DiscoEncoder_30ranuras (Autodesk Fusion 360 design; units mm, degrees)
part number: 2026-10-14-20-40-18-868
Autodesk Fusion 360 part; units mm, degrees
sketch "Boceto6" plane through (0, 0, 0) normal (0, 0, 1) x (1, 0, 0)
  circle A0 centre (0, 0) radius 10
extrude "Extruir6" add sketch "Boceto6" along normal blind 3
sketch "Boceto7" plane through (0, 0, 0) normal (0, 0, 1) x (1, 0, 0)
  arc A0 (2.0347, -1.85) -> (2.0347, 1.85) centre (0, 0) ccw
  line L0 (2.0347, 1.85) -> (-2.0347, 1.85)
  arc A1 (-2.0347, 1.85) -> (-2.0347, -1.85) centre (0, 0) ccw
  line L1 (-2.0347, -1.85) -> (2.0347, -1.85)
extrude "Extruir7" cut sketch "Boceto7" along normal blind 4
sketch "Boceto8" plane through (0, 0, 0) normal (0, 0, 1) x (1, 0, 0)
  arc A0 (6.4911, -0.3402) -> (6.4911, 0.3402) centre (0, 0) ccw
  line L0 (6.4911, 0.3402) -> (8.9877, 0.471)
  arc A1 (8.9877, -0.471) -> (8.9877, 0.471) centre (0, 0) ccw
  line L1 (8.9877, -0.471) -> (6.4911, -0.3402)
  arc A2 (6.42, 1.0168) -> (6.2785, 1.6823) centre (0, 0) ccw
  line L2 (6.2785, 1.6823) -> (8.6933, 2.3294)
  arc A3 (8.8892, 1.4079) -> (8.6933, 2.3294) centre (0, 0) ccw
  line L3 (8.8892, 1.4079) -> (6.42, 1.0168)
  arc A4 (6.0683, 2.3294) -> (5.7915, 2.9509) centre (0, 0) ccw
  line L4 (5.7915, 2.9509) -> (8.0191, 4.0859)
  arc A5 (8.4022, 3.2253) -> (8.0191, 4.0859) centre (0, 0) ccw
  line L5 (8.4022, 3.2253) -> (6.0683, 2.3294)
  arc A6 (5.4514, 3.5402) -> (5.0514, 4.0906) centre (0, 0) ccw
  line L6 (5.0514, 4.0906) -> (6.9943, 5.6639)
  arc A7 (7.548, 4.9018) -> (6.9943, 5.6639) centre (0, 0) ccw
  line L7 (7.548, 4.9018) -> (5.4514, 3.5402)
  arc A8 (4.5962, 4.5962) -> (4.0906, 5.0514) centre (0, 0) ccw
  line L8 (4.0906, 5.0514) -> (5.6639, 6.9943)
  arc A9 (6.364, 6.364) -> (5.6639, 6.9943) centre (0, 0) ccw
  line L9 (6.364, 6.364) -> (4.5962, 4.5962)
  arc A10 (3.5402, 5.4514) -> (2.9509, 5.7915) centre (0, 0) ccw
  line L10 (2.9509, 5.7915) -> (4.0859, 8.0191)
  arc A11 (4.9018, 7.548) -> (4.0859, 8.0191) centre (0, 0) ccw
  line L11 (4.9018, 7.548) -> (3.5402, 5.4514)
  arc A12 (2.3294, 6.0683) -> (1.6823, 6.2785) centre (0, 0) ccw
  line L12 (1.6823, 6.2785) -> (2.3294, 8.6933)
  arc A13 (3.2253, 8.4022) -> (2.3294, 8.6933) centre (0, 0) ccw
  line L13 (3.2253, 8.4022) -> (2.3294, 6.0683)
  arc A14 (1.0168, 6.42) -> (0.3402, 6.4911) centre (0, 0) ccw
  line L14 (0.3402, 6.4911) -> (0.471, 8.9877)
  arc A15 (1.4079, 8.8892) -> (0.471, 8.9877) centre (0, 0) ccw
  line L15 (1.4079, 8.8892) -> (1.0168, 6.42)
  arc A16 (-0.3402, 6.4911) -> (-1.0168, 6.42) centre (0, 0) ccw
  line L16 (-1.0168, 6.42) -> (-1.4079, 8.8892)
  arc A17 (-0.471, 8.9877) -> (-1.4079, 8.8892) centre (0, 0) ccw
  line L17 (-0.471, 8.9877) -> (-0.3402, 6.4911)
  arc A18 (-1.6823, 6.2785) -> (-2.3294, 6.0683) centre (0, 0) ccw
  line L18 (-2.3294, 6.0683) -> (-3.2253, 8.4022)
  arc A19 (-2.3294, 8.6933) -> (-3.2253, 8.4022) centre (0, 0) ccw
  line L19 (-2.3294, 8.6933) -> (-1.6823, 6.2785)
  arc A20 (-2.9509, 5.7915) -> (-3.5402, 5.4514) centre (0, 0) ccw
  line L20 (-3.5402, 5.4514) -> (-4.9018, 7.548)
  arc A21 (-4.0859, 8.0191) -> (-4.9018, 7.548) centre (0, 0) ccw
  line L21 (-4.0859, 8.0191) -> (-2.9509, 5.7915)
  arc A22 (-4.0906, 5.0514) -> (-4.5962, 4.5962) centre (0, 0) ccw
  line L22 (-4.5962, 4.5962) -> (-6.364, 6.364)
  arc A23 (-5.6639, 6.9943) -> (-6.364, 6.364) centre (0, 0) ccw
  line L23 (-5.6639, 6.9943) -> (-4.0906, 5.0514)
  arc A24 (-5.0514, 4.0906) -> (-5.4514, 3.5402) centre (0, 0) ccw
  line L24 (-5.4514, 3.5402) -> (-7.548, 4.9018)
  arc A25 (-6.9943, 5.6639) -> (-7.548, 4.9018) centre (0, 0) ccw
  line L25 (-6.9943, 5.6639) -> (-5.0514, 4.0906)
  arc A26 (-5.7915, 2.9509) -> (-6.0683, 2.3294) centre (0, 0) ccw
  line L26 (-6.0683, 2.3294) -> (-8.4022, 3.2253)
  arc A27 (-8.0191, 4.0859) -> (-8.4022, 3.2253) centre (0, 0) ccw
  line L27 (-8.0191, 4.0859) -> (-5.7915, 2.9509)
  arc A28 (-6.2785, 1.6823) -> (-6.42, 1.0168) centre (0, 0) ccw
  line L28 (-6.42, 1.0168) -> (-8.8892, 1.4079)
  arc A29 (-8.6933, 2.3294) -> (-8.8892, 1.4079) centre (0, 0) ccw
  line L29 (-8.6933, 2.3294) -> (-6.2785, 1.6823)
  arc A30 (-6.4911, 0.3402) -> (-6.4911, -0.3402) centre (0, 0) ccw
  line L30 (-6.4911, -0.3402) -> (-8.9877, -0.471)
  arc A31 (-8.9877, 0.471) -> (-8.9877, -0.471) centre (0, 0) ccw
  line L31 (-8.9877, 0.471) -> (-6.4911, 0.3402)
  arc A32 (-6.42, -1.0168) -> (-6.2785, -1.6823) centre (0, 0) ccw
  line L32 (-6.2785, -1.6823) -> (-8.6933, -2.3294)
  arc A33 (-8.8892, -1.4079) -> (-8.6933, -2.3294) centre (0, 0) ccw
  line L33 (-8.8892, -1.4079) -> (-6.42, -1.0168)
  arc A34 (-6.0683, -2.3294) -> (-5.7915, -2.9509) centre (0, 0) ccw
  line L34 (-5.7915, -2.9509) -> (-8.0191, -4.0859)
  arc A35 (-8.4022, -3.2253) -> (-8.0191, -4.0859) centre (0, 0) ccw
  line L35 (-8.4022, -3.2253) -> (-6.0683, -2.3294)
  arc A36 (-5.4514, -3.5402) -> (-5.0514, -4.0906) centre (0, 0) ccw
  line L36 (-5.0514, -4.0906) -> (-6.9943, -5.6639)
  arc A37 (-7.548, -4.9018) -> (-6.9943, -5.6639) centre (0, 0) ccw
  line L37 (-7.548, -4.9018) -> (-5.4514, -3.5402)
  arc A38 (-4.5962, -4.5962) -> (-4.0906, -5.0514) centre (0, 0) ccw
  line L38 (-4.0906, -5.0514) -> (-5.6639, -6.9943)
  arc A39 (-6.364, -6.364) -> (-5.6639, -6.9943) centre (0, 0) ccw
  line L39 (-6.364, -6.364) -> (-4.5962, -4.5962)
  arc A40 (-3.5402, -5.4514) -> (-2.9509, -5.7915) centre (0, 0) ccw
  line L40 (-2.9509, -5.7915) -> (-4.0859, -8.0191)
  arc A41 (-4.9018, -7.548) -> (-4.0859, -8.0191) centre (0, 0) ccw
  line L41 (-4.9018, -7.548) -> (-3.5402, -5.4514)
  arc A42 (-2.3294, -6.0683) -> (-1.6823, -6.2785) centre (0, 0) ccw
  line L42 (-1.6823, -6.2785) -> (-2.3294, -8.6933)
  arc A43 (-3.2253, -8.4022) -> (-2.3294, -8.6933) centre (0, 0) ccw
  line L43 (-3.2253, -8.4022) -> (-2.3294, -6.0683)
  arc A44 (-1.0168, -6.42) -> (-0.3402, -6.4911) centre (0, 0) ccw
  line L44 (-0.3402, -6.4911) -> (-0.471, -8.9877)
  arc A45 (-1.4079, -8.8892) -> (-0.471, -8.9877) centre (0, 0) ccw
  line L45 (-1.4079, -8.8892) -> (-1.0168, -6.42)
  arc A46 (0.3402, -6.4911) -> (1.0168, -6.42) centre (0, 0) ccw
  line L46 (1.0168, -6.42) -> (1.4079, -8.8892)
  arc A47 (0.471, -8.9877) -> (1.4079, -8.8892) centre (0, 0) ccw
  line L47 (0.471, -8.9877) -> (0.3402, -6.4911)
  arc A48 (1.6823, -6.2785) -> (2.3294, -6.0683) centre (0, 0) ccw
  line L48 (2.3294, -6.0683) -> (3.2253, -8.4022)
  arc A49 (2.3294, -8.6933) -> (3.2253, -8.4022) centre (0, 0) ccw
  line L49 (2.3294, -8.6933) -> (1.6823, -6.2785)
  arc A50 (2.9509, -5.7915) -> (3.5402, -5.4514) centre (0, 0) ccw
  line L50 (3.5402, -5.4514) -> (4.9018, -7.548)
  arc A51 (4.0859, -8.0191) -> (4.9018, -7.548) centre (0, 0) ccw
  line L51 (4.0859, -8.0191) -> (2.9509, -5.7915)
  arc A52 (4.0906, -5.0514) -> (4.5962, -4.5962) centre (0, 0) ccw
  line L52 (4.5962, -4.5962) -> (6.364, -6.364)
  arc A53 (5.6639, -6.9943) -> (6.364, -6.364) centre (0, 0) ccw
  line L53 (5.6639, -6.9943) -> (4.0906, -5.0514)
  arc A54 (5.0514, -4.0906) -> (5.4514, -3.5402) centre (0, 0) ccw
  line L54 (5.4514, -3.5402) -> (7.548, -4.9018)
  arc A55 (6.9943, -5.6639) -> (7.548, -4.9018) centre (0, 0) ccw
  line L55 (6.9943, -5.6639) -> (5.0514, -4.0906)
  arc A56 (5.7915, -2.9509) -> (6.0683, -2.3294) centre (0, 0) ccw
  line L56 (6.0683, -2.3294) -> (8.4022, -3.2253)
  arc A57 (8.0191, -4.0859) -> (8.4022, -3.2253) centre (0, 0) ccw
  line L57 (8.0191, -4.0859) -> (5.7915, -2.9509)
  arc A58 (6.2785, -1.6823) -> (6.42, -1.0168) centre (0, 0) ccw
  line L58 (6.42, -1.0168) -> (8.8892, -1.4079)
  arc A59 (8.6933, -2.3294) -> (8.8892, -1.4079) centre (0, 0) ccw
  line L59 (8.6933, -2.3294) -> (6.2785, -1.6823)
extrude "Extruir8" cut sketch "Boceto8" along normal blind 4
named bodies: "DiscoEncoder"
